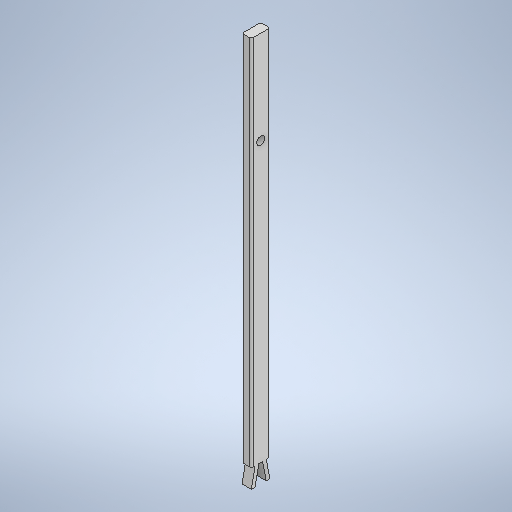
# Autodesk Inventor part: iterasi1
Saved by Autodesk Inventor 2026.2 (Build 302298010, 298A)
## iProperties
Created: 2026-11-09
Part Number: iterasi1
Material: Generic
Document SubType Name: Modeling
Designer: Acer
Density: 1 g/cm^3
Appearance: Default
Author: Acer
Autodesk Inventor part; units mm, degrees
ref_plane "YZ Plane" through (0, 0, 0) normal (1, 0, 0) x (0, 1, 0)
ref_plane "XZ Plane" through (0, 0, 0) normal (0, 1, 0) x (-1, 0, 0)
ref_plane "XY Plane" through (0, 0, 0) normal (0, 0, 1) x (1, 0, 0)
sketch "Sketch1" plane through (0, 0, 0) normal (1, 0, 0) x (0, 1, 0)
  line L0 (-200, 0) -> (200, 0)
  line L1 (200, -10) -> (200, 10)
  line L2 (200, 10) -> (-200, 10)
  line L3 (-200, 10) -> (-200, -10)
  line L4 (-200, -10) -> (200, -10)
  line L5 (200, -10) -> (200, 10)
  line L6 (200, 0) -> (100, 0)
  circle A0 centre (100, 0) radius 4.3
  point P0 (0, 0)
  dimension "d0" = 400
  dimension "d1" = 20
  dimension "d2" = 100
  dimension "d3" = 8.6
  constraints: 14 end point, 2 horizontal, 2 midpoint, 2 parallel, 2 perpendicular, 1 centre point, 1 coincident, 1 point on line
  measures "d0" distance of L0.start L0.end
  measures "d1" distance of L1.start L1.end
  measures "d2" distance of L0.end L6.end
  measures "d3" diameter of A0
extrude "Extrusion1" add sketch "Sketch1" along normal mid plane 10 contours A0 L0 L3 L2 L1 | L0 L1 L4 L3 A0
sketch "Sketch2" plane through (5, 0, 0) normal (1, 0, 0) x (0, 0, -1)
  line L0 (-10, -200) -> (10, -200) projected
  line L1 (0, -220) -> (0, -180)
  line L2 (-10, -200) -> (-6, -200)
  line L3 (-6, -200) -> (-10, -220)
  line L4 (-10, -220) -> (-6.001, -220.0914)
  line L5 (-6, -200) -> (-2, -200)
  line L6 (-2, -200) -> (-6.001, -220.0914)
  line L7 (-2, -200) -> (-6, -200)
  line L8 (6, -200) -> (10, -220)
  line L9 (10, -220) -> (6.001, -220.0914)
  line L10 (2, -200) -> (6.001, -220.0914)
  point P0 (0, 0)
  point P1 (0, -200)
  dimension "d6" = 40
  dimension "d8" = 4
  dimension "d9" = 80
  dimension "d10" = 4
  constraints: 20 end point, 4 symmetric about line, 2 midpoint, 2 point on line, 1 collinear, 1 vertical
  measures "d6" distance of L1.start L1.end
  measures "d8" distance of L3.end L4.end
  measures "d9" angle of L4 L3
  measures "d10" distance of L2.end L5.end
extrude "Extrusion2" add sketch "Sketch2" against normal blind 10
fillet "Fillet1" radius 2 4 edges at (-5, 0, 10) (5, 0, 10) (-5, 0, -10) (5, 0, -10)
body "Solid1"
